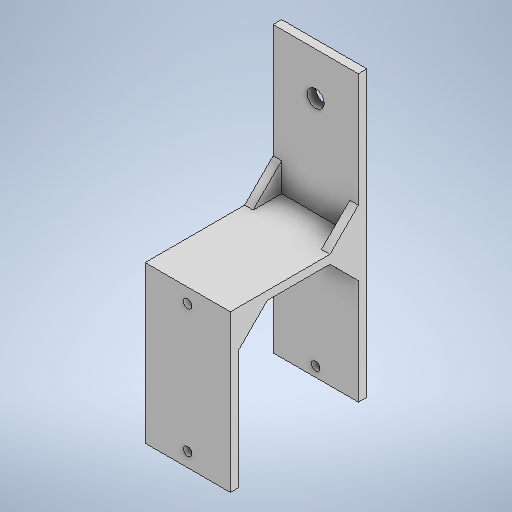
# Autodesk Inventor part: Skull_base
Saved by Autodesk Inventor 2025 (Build 290162000, 162)
## iProperties
Created: 2026-11-09
Part Number: Skull_base
Material: Generic
Document SubType Name: Modeling
Designer: diego
Density: 1 g/cm^3
Appearance: Default
Author: diego
Autodesk Inventor part; units mm, degrees
ref_plane "YZ Plane" through (0, 0, 0) normal (1, 0, 0) x (0, 1, 0)
ref_plane "XZ Plane" through (0, 0, 0) normal (0, 1, 0) x (-1, 0, 0)
ref_plane "XY Plane" through (0, 0, 0) normal (0, 0, 1) x (1, 0, 0)
sketch "Sketch1" plane through (0, 0, 0) normal (0, 0, 1) x (1, 0, 0)
  line L0 (-15, 27.5) -> (15, 27.5)
  line L1 (15, 27.5) -> (15, -27.5)
  line L2 (15, -27.5) -> (-15, -27.5)
  line L3 (-15, -27.5) -> (-15, 27.5)
  line L4 (-15, 27.5) -> (15, -27.5) construction
  line L5 (15, 27.5) -> (-15, -27.5) construction
  point P0 (0, 0)
  dimension "d0" = 30
  dimension "d1" = 55
  constraints: 12 end point, 2 midpoint, 2 parallel, 1 horizontal, 1 perpendicular
  measures "d0" distance of L1.end L2.end
  measures "d1" distance of L0.end L1.end
extrude "Extrusion1" add sketch "Sketch1" along normal blind 3
sketch "Sketch2" plane through (0, 0, 3) normal (0, 0, 1) x (1, 0, 0)
  line L0 (15, 27.5) -> (-15, 27.5) projected
  line L1 (0, 27.5) -> (0, -27.5) construction
  line L2 (-15, -27.5) -> (15, -27.5) projected
  line L3 (15, -27.5) -> (15, 27.5) projected
  line L4 (15, 27.5) -> (-15, 27.5) projected
  line L5 (-15, 27.5) -> (-15, -27.5) projected
  line L6 (-15, -27.5) -> (15, -27.5) projected
  circle A0 centre (0, 22.5) radius 1.5
  circle A1 centre (0, -22.5) radius 1.5
  line L7 (0, 22.5) -> (0, -22.5) construction
  point P0 (0, 0)
  point P1 (0, 0)
  dimension "d4" = 3
  dimension "d5" = 3
  dimension "d6" = 45
  constraints: 4 end point, 4 midpoint, 2 centre point, 2 point on line, 1 collinear, 1 vertical
  measures "d4" diameter of A0
  measures "d5" diameter of A1
  measures "d6" distance of L7.end L7.start
extrude "Extrusion2" cut sketch "Sketch2" against normal through all contours A0 | A1
sketch "Sketch3" plane through (0, 0, 0) normal (0, 0, -1) x (-1, 0, 0)
  point P0 (0, 0)
sketch "Sketch4" plane through (0, 0, 0) normal (0, 0, -1) x (-1, 0, 0)
  circle A0 centre (0, -22.5) radius 1.5 projected
  circle A1 centre (0, 22.5) radius 1.5 projected
  line L0 (15, -27.5) -> (-15, -27.5) projected
  line L1 (15, 27.5) -> (15, -27.5) projected
  line L2 (-15, 27.5) -> (15, 27.5) projected
  line L3 (-15, -27.5) -> (-15, 27.5) projected
  line L4 (-15, 27.5) -> (15, 27.5)
  line L5 (15, 27.5) -> (15, 24.5)
  line L6 (15, 24.5) -> (-15, 24.5)
  line L7 (-15, 24.5) -> (-15, 27.5)
  point P0 (0, 0)
  point P1 (-15, 24.5)
  dimension "d9" = 3
  constraints: 8 end point, 2 parallel, 1 horizontal, 1 perpendicular, 1 point on line
  measures "d9" distance between parallel lines of L6 L2
extrude "Extrusion3" add sketch "Sketch4" along normal blind 45 contours L6 L3 L2 L1
sketch "Sketch5" plane through (-15, 27.5, 3) normal (0, 1, 0) x (1, 0, 0)
  line L0 (0, 48) -> (0, 0) projected
  line L1 (30, 0) -> (0, 0) projected
  line L2 (30, 48) -> (30, 0) projected
  line L3 (0, 48) -> (30, 48) projected
  line L4 (30, 48) -> (0, 48)
  line L5 (0, 48) -> (0, 45)
  line L6 (0, 45) -> (30, 45)
  line L7 (30, 45) -> (30, 48)
  point P0 (15, 3)
  dimension "d12" = 3
  constraints: 8 end point, 2 parallel, 1 horizontal, 1 perpendicular, 1 point on line
  measures "d12" distance of L5.end L4.end
extrude "Extrusion4" add sketch "Sketch5" along normal blind 50 and the other way blind 50 contours L3 L2 L6 L0
sketch "Sketch7" plane through (-15, 27.5, -42) normal (0, 0, 1) x (1, 0, 0)
  line L0 (30, 0) -> (0, 0) projected
  line L1 (30, 50) -> (30, 0) projected
  line L2 (0, 50) -> (30, 50) projected
  line L3 (0, 0) -> (0, 50) projected
  circle A0 centre (15, 35) radius 3
  line L4 (15, 0) -> (15, 50) construction
  point P0 (15, -27.5)
  dimension "d15" = 6
  dimension "d16" = 35
  constraints: 2 end point, 2 midpoint, 1 centre point, 1 point on line
  measures "d15" diameter of A0
  measures "d16" distance from line of A0.centre L0
extrude "Extrusion5" cut sketch "Sketch7" against normal blind 50 contours A0
sketch "Sketch8" plane through (-15, 24.5, -42) normal (0, 0, 1) x (1, 0, 0)
  line L0 (0, 0) -> (30, 0) projected
  line L1 (0, -47) -> (0, 0) projected
  line L2 (30, -47) -> (0, -47) projected
  line L3 (30, 0) -> (30, -47) projected
  line L4 (0, -47) -> (0, 0) projected
  line L5 (15, -47) -> (15, 0) construction
  line L6 (0, -23.5) -> (30, -23.5) construction
  line L7 (30, 0) -> (30, -47) projected
  circle A0 centre (15, -43.5) radius 1.5
  line L8 (15, 0) -> (15, -47) construction
  circle A1 centre (15, -3.5) radius 1.5
  dimension "d24" = 3
  dimension "d25" = 40
  constraints: 6 end point, 4 midpoint, 3 symmetric about line, 2 centre point, 2 point on line, 1 other
  measures "d24" diameter of A0
  measures "d25" distance of A0.centre A1.centre
extrude "Extrusion6" cut sketch "Sketch8" against normal blind 50 contours A0 | A1
sketch "Sketch9" plane through (-15, 27.5, -42) normal (0, 0, 1) x (1, 0, 0)
  circle A0 centre (15, 35) radius 3 projected
  line L0 (30, 0) -> (0, 0) projected
  line L1 (30, 50) -> (30, 0) projected
  line L2 (0, 50) -> (30, 50) projected
  line L3 (0, 0) -> (0, 50) projected
  circle A1 centre (15, -6.5) radius 1.5 projected
  circle A2 centre (15, -46.5) radius 1.5 projected
  line L4 (0, -3) -> (30, -3) projected
  line L5 (0, -50) -> (0, -3) projected
  line L6 (30, -50) -> (0, -50) projected
  line L7 (30, -3) -> (30, -50) projected
  line L8 (0, 0) -> (3, 0)
  line L9 (3, 0) -> (3, 10)
  line L10 (3, 10) -> (0, 10)
  line L11 (0, 10) -> (0, 0)
  line L12 (30, 0) -> (27, 0)
  line L13 (27, 0) -> (27, 10)
  line L14 (27, 10) -> (30, 10)
  line L15 (30, 10) -> (30, 0)
  line L16 (0, -3) -> (3, -3)
  line L17 (3, -3) -> (3, -13)
  line L18 (3, -13) -> (0, -13)
  line L19 (0, -13) -> (0, -3)
  line L20 (30, -3) -> (30, -50) projected
  line L21 (30, -3) -> (27, -3)
  line L22 (27, -3) -> (27, -13)
  line L23 (27, -13) -> (30, -13)
  line L24 (30, -13) -> (30, -3)
  point P0 (15, -27.5)
  dimension "d28" = 3
  dimension "d29" = 10
  dimension "d30" = 3
  dimension "d31" = 10
  dimension "d32" = 3
  dimension "d33" = 10
  dimension "d34" = 3
  dimension "d35" = 10
  constraints: 32 end point, 8 parallel, 4 horizontal, 4 perpendicular
  measures "d28" distance of L10.end L9.end
  measures "d29" distance of L9.end L8.end
  measures "d30" distance of L13.end L14.end
  measures "d31" distance of L12.end L13.end
  measures "d32" distance of L17.end L18.end
  measures "d33" distance of L16.end L17.end
  measures "d34" distance of L23.end L22.end
  measures "d35" distance of L22.end L21.end
extrude "Extrusion7" add sketch "Sketch9" along normal blind 10 contours L0 L13 L14 L1 | L0 L3 L10 L9 | L4 L17 L18 L5 | L4 L7 L23 L22
sketch "Sketch10" plane through (0, 0, 0) normal (0, 0, -1) x (-1, 0, 0)
  line L0 (15, 24.5) -> (-15, 24.5) projected
  line L1 (-15, -27.5) -> (-15, 24.5) projected
  line L2 (15, -27.5) -> (-15, -27.5) projected
  line L3 (15, 24.5) -> (15, -27.5) projected
  circle A0 centre (0, -22.5) radius 1.5 projected
  circle A1 centre (0, 22.5) radius 1.5 projected
  line L4 (15, 24.5) -> (-15, 24.5) projected
  line L5 (-15, 24.5) -> (-12, 24.5)
  line L6 (-12, 24.5) -> (-12, 14.5)
  line L7 (-12, 14.5) -> (-15, 14.5)
  line L8 (-15, 14.5) -> (-15, 24.5)
  line L9 (15, 24.5) -> (12, 24.5)
  line L10 (12, 24.5) -> (12, 14.5)
  line L11 (12, 14.5) -> (15, 14.5)
  line L12 (15, 14.5) -> (15, 24.5)
  point P0 (0, 0)
  dimension "d38" = 3
  dimension "d39" = 10
  dimension "d40" = 3
  dimension "d41" = 10
  constraints: 16 end point, 4 parallel, 2 horizontal, 2 perpendicular
  measures "d38" distance of L6.end L7.end
  measures "d39" distance of L5.end L6.end
  measures "d40" distance of L11.end L10.end
  measures "d41" distance of L10.end L9.end
extrude "Extrusion8" add sketch "Sketch10" along normal blind 10 contours L3 L11 L10 L0 | L6 L7 L1 L0
sketch "Sketch11" plane through (15, -27.5, 3) normal (1, 0, 0) x (0, 0, -1)
  line L0 (35, 55) -> (0, 55) projected
  line L1 (0, 0) -> (0, 55) projected
  line L2 (3, 0) -> (0, 0) projected
  line L3 (3, 0) -> (3, 42) projected
  line L4 (3, 42) -> (13, 42) projected
  line L5 (13, 52) -> (13, 42) projected
  line L6 (13, 52) -> (35, 52) projected
  line L7 (35, 42) -> (35, 52) projected
  line L8 (45, 42) -> (35, 42) projected
  line L9 (45, 42) -> (45, 5) projected
  line L10 (48, 5) -> (45, 5) projected
  line L11 (48, 5) -> (48, 105) projected
  line L12 (45, 105) -> (48, 105) projected
  line L13 (45, 105) -> (45, 65) projected
  line L14 (45, 65) -> (35, 65) projected
  line L15 (35, 55) -> (35, 65) projected
  line L16 (3, 42) -> (13, 52)
  line L17 (45, 42) -> (35, 52)
  line L18 (35, 55) -> (45, 65)
  point P0 (3, 27.5)
  constraints: 6 end point, 2 perpendicular
extrude "Extrusion9" cut sketch "Sketch11" against normal through all contours L15 L14 L18 | L16 L5 L4 | L17 L8 L7
body "Solid1"
